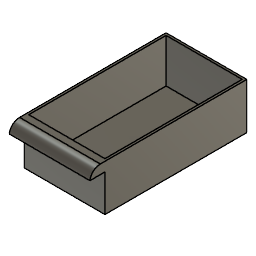
Z-Tray (Autodesk Fusion 360 design; units mm, degrees)
Autodesk Fusion 360 part; units mm, degrees
sketch "Sketch1" plane through (0, 0, 0) normal (0, 1, 0) x (1, 0, 0)
  line L0 (0, 0) -> (70, 0)
  line L1 (70, 0) -> (70, -40)
  line L2 (70, -40) -> (0, -40)
  line L3 (0, -40) -> (0, 0)
  dimension "d1" = 70
  dimension "d2" = 40
  constraint horizontal L0
  constraint vertical L1
  constraint horizontal L2
  constraint vertical L3
  constraint coincident L0.start L3.end
  measures "d1" distance of L0.start L0.end
  measures "d2" distance of L0.start L2.end
extrude "Extrude1" add sketch "Sketch1" along normal blind 123
shell "Shell1" thickness 2 removed faces 1 at (46.6667, 41, 40)
sketch "Sketch2" plane through (0, 0, 0) normal (-1, 0, 0) x (0, -1, 0)
  line L0 (0, 0) -> (0, 40)
  line L1 (0, 40) -> (-123, 40)
  line L2 (-123, 40) -> (-123, 0)
  line L3 (-123, 0) -> (0, 0)
  line L4 (0, 40) -> (4, 40)
  arc A0 (13, 32) -> (4, 40) centre (4, 30.9375) ccw
  line L5 (13, 32) -> (0, 32)
  constraint coincident L0.end L1.start
  constraint perpendicular L0 L4
  constraint tangent L4 A0
  constraint coincident L0 L5.end
  constraint perpendicular L0 L5
extrude "Extrude2" add sketch "Sketch2" against normal blind 70 contours L0 L4 A0 L5
shell "Shell2" thickness 2 removed faces 1 at (23.3333, -8.6667, 32)
